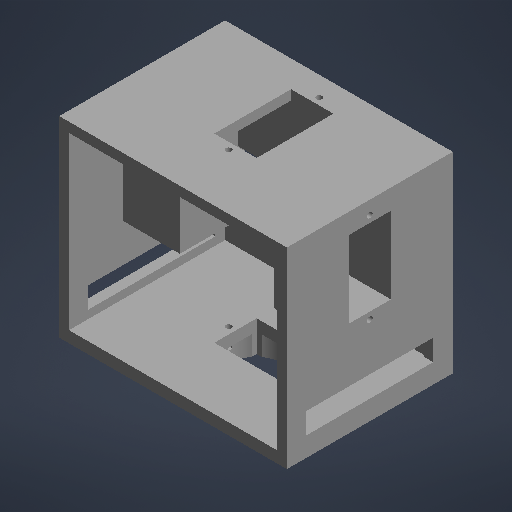
# Autodesk Inventor part: R2_torso
Saved by Autodesk Inventor 2027 (Build 310192060, 192F)
## iProperties
Part Number: R2_torso
Material: Genérico
Document SubType Name: Modelado
Designer: rodri
Appearance: Por defecto
Author: rodri
Autodesk Inventor part; units mm, degrees
ref_plane "Plano de trabajo1" through (0, 0, -25.5) normal (0, 0, 1) x (1, 0, 0)
sketch "Boceto1" plane through (0, 0, -25.5) normal (0, 0, 1) x (1, 0, 0)
  line L0 (-35, 6.5) -> (35, 6.5)
  line L1 (35, 6.5) -> (35, 10)
  line L2 (35, 10) -> (-35, 10)
  line L3 (-35, 10) -> (-35, 6.5)
  constraints: 8 end point, 2 parallel, 1 horizontal, 1 perpendicular
extrude "Extrusión1" add sketch "Boceto1" along normal blind 51
ref_plane "Plano de trabajo2" through (0, 0.5, 0) normal (0, 1, 0) x (-1, 0, 0)
sketch "Boceto2" plane through (0, 0.5, 0) normal (0, 1, 0) x (-1, 0, 0)
  circle A0 centre (0, 0) radius 18
  constraints: 1 centre point
extrude "Extrusión2" add sketch "Boceto2" along normal blind 6.01
ref_plane "Plano de trabajo3" through (0, 0.4, 0) normal (0, 1, 0) x (-1, 0, 0)
sketch "Boceto3" plane through (0, 0.4, 0) normal (0, 1, 0) x (-1, 0, 0)
  circle A0 centre (0, 0) radius 8
  constraints: 1 centre point
extrude "Extrusión3" cut sketch "Boceto3" along normal blind 6.12
ref_plane "Plano de trabajo4" through (0, 0, -25.5) normal (0, 0, 1) x (1, 0, 0)
sketch "Boceto4" plane through (0, 0, -25.5) normal (0, 0, 1) x (1, 0, 0)
  line L0 (-35, 6.5) -> (-32, 6.5)
  line L1 (-32, 6.5) -> (-32, 65.5)
  line L2 (-32, 65.5) -> (-35, 65.5)
  line L3 (-35, 65.5) -> (-35, 6.5)
  constraints: 8 end point, 2 parallel, 1 horizontal, 1 perpendicular
extrude "Extrusión4" add sketch "Boceto4" along normal blind 51
ref_plane "Plano de trabajo5" through (0, 0, -25.5) normal (0, 0, 1) x (1, 0, 0)
sketch "Boceto5" plane through (0, 0, -25.5) normal (0, 0, 1) x (1, 0, 0)
  line L0 (32, 6.5) -> (35, 6.5)
  line L1 (35, 6.5) -> (35, 65.5)
  line L2 (35, 65.5) -> (32, 65.5)
  line L3 (32, 65.5) -> (32, 6.5)
  constraints: 8 end point, 2 parallel, 1 horizontal, 1 perpendicular
extrude "Extrusión5" add sketch "Boceto5" along normal blind 51
ref_plane "Plano de trabajo6" through (0, 0, -25.5) normal (0, 0, 1) x (1, 0, 0)
sketch "Boceto6" plane through (0, 0, -25.5) normal (0, 0, 1) x (1, 0, 0)
  line L0 (-35, 6.5) -> (35, 6.5)
  line L1 (35, 6.5) -> (35, 65.5)
  line L2 (35, 65.5) -> (-35, 65.5)
  line L3 (-35, 65.5) -> (-35, 6.5)
  constraints: 8 end point, 2 parallel, 1 horizontal, 1 perpendicular
extrude "Extrusión6" add sketch "Boceto6" along normal blind 3
ref_plane "Plano de trabajo7" through (0, 0, -25.5) normal (0, 0, 1) x (1, 0, 0)
sketch "Boceto7" plane through (0, 0, -25.5) normal (0, 0, 1) x (1, 0, 0)
  line L0 (-35, 62.5) -> (35, 62.5)
  line L1 (35, 62.5) -> (35, 65.5)
  line L2 (35, 65.5) -> (-35, 65.5)
  line L3 (-35, 65.5) -> (-35, 62.5)
  constraints: 8 end point, 2 parallel, 1 horizontal, 1 perpendicular
extrude "Extrusión7" add sketch "Boceto7" along normal blind 51
ref_plane "Plano de trabajo8" through (0, 0, -25.6) normal (0, 0, 1) x (1, 0, 0)
sketch "Boceto8" plane through (0, 0, -25.6) normal (0, 0, 1) x (1, 0, 0)
  line L0 (-29, 14.5) -> (29, 14.5)
  line L1 (29, 14.5) -> (29, 37)
  line L2 (29, 37) -> (-29, 37)
  line L3 (-29, 37) -> (-29, 14.5)
  constraints: 8 end point, 2 parallel, 1 horizontal, 1 perpendicular
extrude "Extrusión8" cut sketch "Boceto8" along normal blind 3.2
ref_plane "Plano de trabajo9" through (0, 0, -19.5) normal (0, 0, 1) x (1, 0, 0)
sketch "Boceto9" plane through (0, 0, -19.5) normal (0, 0, 1) x (1, 0, 0)
  line L0 (31.9, 12.5) -> (35.1, 12.5)
  line L1 (35.1, 12.5) -> (35.1, 19)
  line L2 (35.1, 19) -> (31.9, 19)
  line L3 (31.9, 19) -> (31.9, 12.5)
  constraints: 8 end point, 2 parallel, 1 horizontal, 1 perpendicular
extrude "Extrusión9" cut sketch "Boceto9" along normal blind 39
ref_plane "Plano de trabajo10" through (0, 0, -19.5) normal (0, 0, 1) x (1, 0, 0)
sketch "Boceto10" plane through (0, 0, -19.5) normal (0, 0, 1) x (1, 0, 0)
  line L0 (-35.1, 12.5) -> (-31.9, 12.5)
  line L1 (-31.9, 12.5) -> (-31.9, 19)
  line L2 (-31.9, 19) -> (-35.1, 19)
  line L3 (-35.1, 19) -> (-35.1, 12.5)
  constraints: 8 end point, 2 parallel, 1 horizontal, 1 perpendicular
extrude "Extrusión10" cut sketch "Boceto10" along normal blind 39
ref_plane "Plano de trabajo11" through (0, 0, -6.5) normal (0, 0, 1) x (1, 0, 0)
sketch "Boceto11" plane through (0, 0, -6.5) normal (0, 0, 1) x (1, 0, 0)
  line L0 (-6.3, -0.5) -> (17.3, -0.5)
  line L1 (17.3, -0.5) -> (17.3, 10.1)
  line L2 (17.3, 10.1) -> (-6.3, 10.1)
  line L3 (-6.3, 10.1) -> (-6.3, -0.5)
  constraints: 8 end point, 2 parallel, 1 horizontal, 1 perpendicular
extrude "Extrusión11" cut sketch "Boceto11" along normal blind 13
ref_plane "Plano de trabajo12" through (0, 4, 0) normal (0, 1, 0) x (-1, 0, 0)
sketch "Boceto12" plane through (0, 4, 0) normal (0, 1, 0) x (-1, 0, 0)
  circle A0 centre (-19.4, 0) radius 0.85
  constraints: 1 centre point
extrude "Extrusión12" cut sketch "Boceto12" along normal blind 6.1
ref_plane "Plano de trabajo13" through (0, 4, 0) normal (0, 1, 0) x (-1, 0, 0)
sketch "Boceto13" plane through (0, 4, 0) normal (0, 1, 0) x (-1, 0, 0)
  circle A0 centre (8.4, 0) radius 0.85
  constraints: 1 centre point
extrude "Extrusión13" cut sketch "Boceto13" along normal blind 6.1
ref_plane "Plano de trabajo14" through (0, 0, -17.3) normal (0, 0, 1) x (1, 0, 0)
sketch "Boceto14" plane through (0, 0, -17.3) normal (0, 0, 1) x (1, 0, 0)
  line L0 (-6.5, 46.5) -> (6.5, 46.5)
  line L1 (6.5, 46.5) -> (6.5, 65.6)
  line L2 (6.5, 65.6) -> (-6.5, 65.6)
  line L3 (-6.5, 65.6) -> (-6.5, 46.5)
  constraints: 8 end point, 2 parallel, 1 horizontal, 1 perpendicular
extrude "Extrusión14" cut sketch "Boceto14" along normal blind 23.6
ref_plane "Plano de trabajo15" through (0, 59.5, 0) normal (0, 1, 0) x (-1, 0, 0)
sketch "Boceto15" plane through (0, 59.5, 0) normal (0, 1, 0) x (-1, 0, 0)
  circle A0 centre (0, -19.4) radius 0.85
  constraints: 1 centre point
extrude "Extrusión15" cut sketch "Boceto15" along normal blind 6.1
ref_plane "Plano de trabajo16" through (0, 59.5, 0) normal (0, 1, 0) x (-1, 0, 0)
sketch "Boceto16" plane through (0, 59.5, 0) normal (0, 1, 0) x (-1, 0, 0)
  circle A0 centre (0, 8.4) radius 0.85
  constraints: 1 centre point
extrude "Extrusión16" cut sketch "Boceto16" along normal blind 6.1
ref_plane "Plano de trabajo17" through (0, 0, -9) normal (0, 0, 1) x (1, 0, 0)
sketch "Boceto17" plane through (0, 0, -9) normal (0, 0, 1) x (1, 0, 0)
  line L0 (14.4, 30.9) -> (35, 30.9)
  line L1 (35, 30.9) -> (35, 64.1)
  line L2 (35, 64.1) -> (14.4, 64.1)
  line L3 (14.4, 64.1) -> (14.4, 30.9)
  constraints: 8 end point, 2 parallel, 1 horizontal, 1 perpendicular
extrude "Extrusión17" add sketch "Boceto17" along normal blind 18
ref_plane "Plano de trabajo18" through (0, 0, -6.5) normal (0, 0, 1) x (1, 0, 0)
sketch "Boceto18" plane through (0, 0, -6.5) normal (0, 0, 1) x (1, 0, 0)
  line L0 (16.9, 35.7) -> (35.1, 35.7)
  line L1 (35.1, 35.7) -> (35.1, 59.3)
  line L2 (35.1, 59.3) -> (16.9, 59.3)
  line L3 (16.9, 59.3) -> (16.9, 35.7)
  constraints: 8 end point, 2 parallel, 1 horizontal, 1 perpendicular
extrude "Extrusión18" cut sketch "Boceto18" along normal blind 13
ref_plane "Plano de trabajo19" through (0, 0, -3.5) normal (0, 0, 1) x (1, 0, 0)
sketch "Boceto19" plane through (0, 0, -3.5) normal (0, 0, 1) x (1, 0, 0)
  line L0 (16.9, 30.5) -> (21.9, 30.5)
  line L1 (21.9, 30.5) -> (21.9, 37.5)
  line L2 (21.9, 37.5) -> (16.9, 37.5)
  line L3 (16.9, 37.5) -> (16.9, 30.5)
  constraints: 8 end point, 2 parallel, 1 horizontal, 1 perpendicular
extrude "Extrusión19" cut sketch "Boceto19" along normal blind 7
ref_plane "Plano de trabajo20" through (29, 0, 0) normal (1, 0, 0) x (0, 1, 0)
sketch "Boceto20" plane through (29, 0, 0) normal (1, 0, 0) x (0, 1, 0)
  circle A0 centre (33.6, 0) radius 0.85
  constraints: 1 centre point
extrude "Extrusión20" cut sketch "Boceto20" along normal blind 6.1
ref_plane "Plano de trabajo21" through (29, 0, 0) normal (1, 0, 0) x (0, 1, 0)
sketch "Boceto21" plane through (29, 0, 0) normal (1, 0, 0) x (0, 1, 0)
  circle A0 centre (61.4, 0) radius 0.85
  constraints: 1 centre point
extrude "Extrusión21" cut sketch "Boceto21" along normal blind 6.1
ref_plane "Plano de trabajo22" through (0, 0, -6.5) normal (0, 0, 1) x (1, 0, 0)
sketch "Boceto22" plane through (0, 0, -6.5) normal (0, 0, 1) x (1, 0, 0)
  line L0 (28, 35.7) -> (35.2, 35.7)
  line L1 (35.2, 35.7) -> (35.2, 59.3)
  line L2 (35.2, 59.3) -> (28, 59.3)
  line L3 (28, 59.3) -> (28, 35.7)
  constraints: 8 end point, 2 parallel, 1 horizontal, 1 perpendicular
extrude "Extrusión22" cut sketch "Boceto22" along normal blind 13
ref_plane "Plano de trabajo23" through (0, 0, -9) normal (0, 0, 1) x (1, 0, 0)
sketch "Boceto23" plane through (0, 0, -9) normal (0, 0, 1) x (1, 0, 0)
  line L0 (-35, 30.9) -> (-14.4, 30.9)
  line L1 (-14.4, 30.9) -> (-14.4, 64.1)
  line L2 (-14.4, 64.1) -> (-35, 64.1)
  line L3 (-35, 64.1) -> (-35, 30.9)
  constraints: 8 end point, 2 parallel, 1 horizontal, 1 perpendicular
extrude "Extrusión23" add sketch "Boceto23" along normal blind 18
ref_plane "Plano de trabajo24" through (0, 0, -6.5) normal (0, 0, 1) x (1, 0, 0)
sketch "Boceto24" plane through (0, 0, -6.5) normal (0, 0, 1) x (1, 0, 0)
  line L0 (-35.1, 35.7) -> (-16.9, 35.7)
  line L1 (-16.9, 35.7) -> (-16.9, 59.3)
  line L2 (-16.9, 59.3) -> (-35.1, 59.3)
  line L3 (-35.1, 59.3) -> (-35.1, 35.7)
  constraints: 8 end point, 2 parallel, 1 horizontal, 1 perpendicular
extrude "Extrusión24" cut sketch "Boceto24" along normal blind 13
ref_plane "Plano de trabajo25" through (0, 0, -3.5) normal (0, 0, 1) x (1, 0, 0)
sketch "Boceto25" plane through (0, 0, -3.5) normal (0, 0, 1) x (1, 0, 0)
  line L0 (-21.9, 30.5) -> (-16.9, 30.5)
  line L1 (-16.9, 30.5) -> (-16.9, 37.5)
  line L2 (-16.9, 37.5) -> (-21.9, 37.5)
  line L3 (-21.9, 37.5) -> (-21.9, 30.5)
  constraints: 8 end point, 2 parallel, 1 horizontal, 1 perpendicular
extrude "Extrusión25" cut sketch "Boceto25" along normal blind 7
ref_plane "Plano de trabajo26" through (-35.1, 0, 0) normal (1, 0, 0) x (0, 1, 0)
sketch "Boceto26" plane through (-35.1, 0, 0) normal (1, 0, 0) x (0, 1, 0)
  circle A0 centre (33.6, 0) radius 0.85
  constraints: 1 centre point
extrude "Extrusión26" cut sketch "Boceto26" along normal blind 6.1
ref_plane "Plano de trabajo27" through (-35.1, 0, 0) normal (1, 0, 0) x (0, 1, 0)
sketch "Boceto27" plane through (-35.1, 0, 0) normal (1, 0, 0) x (0, 1, 0)
  circle A0 centre (61.4, 0) radius 0.85
  constraints: 1 centre point
extrude "Extrusión27" cut sketch "Boceto27" along normal blind 6.1
ref_plane "Plano de trabajo28" through (0, 0, -6.5) normal (0, 0, 1) x (1, 0, 0)
sketch "Boceto28" plane through (0, 0, -6.5) normal (0, 0, 1) x (1, 0, 0)
  line L0 (-35.2, 35.7) -> (-28, 35.7)
  line L1 (-28, 35.7) -> (-28, 59.3)
  line L2 (-28, 59.3) -> (-35.2, 59.3)
  line L3 (-35.2, 59.3) -> (-35.2, 35.7)
  constraints: 8 end point, 2 parallel, 1 horizontal, 1 perpendicular
extrude "Extrusión28" cut sketch "Boceto28" along normal blind 13
